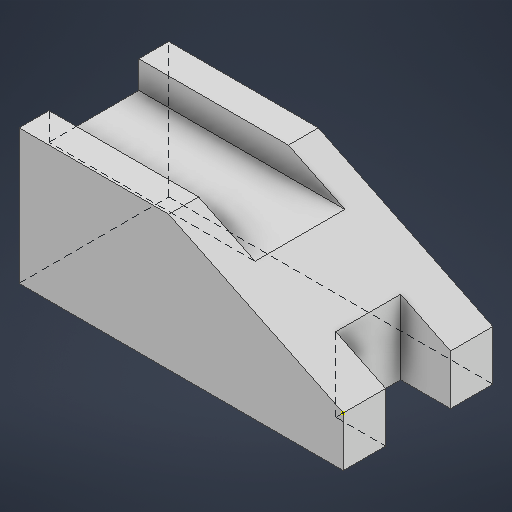
# Autodesk Inventor part: part tree
Saved by Autodesk Inventor 2027 (Build 310192060, 192F)
## iProperties
Created: 2026-10-29
Part Number: part tree
Material: Generic
Document SubType Name: Modeling
Designer: 6100673
Density: 1 g/cm^3
Appearance: Default
Author: 6100673
Autodesk Inventor part; units mm, degrees
ref_plane "YZ Plane" through (0, 0, 0) normal (1, 0, 0) x (0, 1, 0)
ref_plane "XZ Plane" through (0, 0, 0) normal (0, 1, 0) x (-1, 0, 0)
ref_plane "XY Plane" through (0, 0, 0) normal (0, 0, 1) x (1, 0, 0)
sketch "Sketch1" plane through (0, 0, 0) normal (0, 0, 1) x (1, 0, 0)
  line L0 (0, 0) -> (0, -20)
  line L1 (0, -20) -> (-130, -20)
  line L2 (-130, -20) -> (-130, 34)
  line L3 (-130, 34) -> (-70, 34)
  line L4 (-70, 34) -> (0, 0)
  dimension "d0" = 20
  dimension "d1" = 130
  dimension "d2" = 54
  dimension "d3" = 60
  constraints: 10 end point, 3 perpendicular, 1 vertical
  measures "d0" distance of L0.start L0.end
  measures "d1" distance of L0.end L1.end
  measures "d2" distance of L1.end L2.end
  measures "d3" distance of L2.end L3.end
extrude "Extrusion1" add sketch "Sketch1" against normal blind 60
sketch "Sketch2" plane through (0, 0, 0) normal (0.4369, 0.8995, 0) x (0.8995, -0.4369, 0)
  point P0 (0, 0)
sketch "Sketch3" plane through (-130, 34, 0) normal (0, 1, 0) x (1, 0, 0)
  line L0 (130, 0) -> (60, 0) projected
  line L1 (130, 0) -> (130, 60) projected
  line L2 (130, 0) -> (110, 0) construction
  line L3 (110, 17) -> (130, 17)
  line L4 (110, 17) -> (110, 43)
  line L5 (110, 43) -> (130, 43)
  dimension "d8" = 17
  dimension "d9" = 26
  constraints: 8 end point, 3 point on line, 2 perpendicular, 1 vertical
  measures "d8" distance of L2.end L3.start
  measures "d9" distance of L3.start L4.end
extrude "Extrusion2" cut sketch "Sketch3" against normal blind 60
sketch "Sketch4" plane through (0, -20, 0) normal (1, 0, 0) x (0, 0, -1)
  line L0 (0, 54) -> (60, 54) projected
  line L1 (0, 54) -> (12, 54) construction
  line L2 (12, 54) -> (12, 43)
  line L3 (12, 43) -> (48, 43)
  line L4 (48, 43) -> (48, 54)
  line L5 (60, 54) -> (12, 54) construction
  point P0 (0, 20)
  dimension "d12" = 12
  dimension "d13" = 11
  dimension "d14" = 36
  constraints: 10 end point, 4 perpendicular, 2 point on line
  measures "d12" distance of L0.start L1.end
  measures "d13" distance of L1.end L2.end
  measures "d14" distance of L2.end L3.end
extrude "Extrusion3" cut sketch "Sketch4" against normal blind 144.75
body "Solid1"
